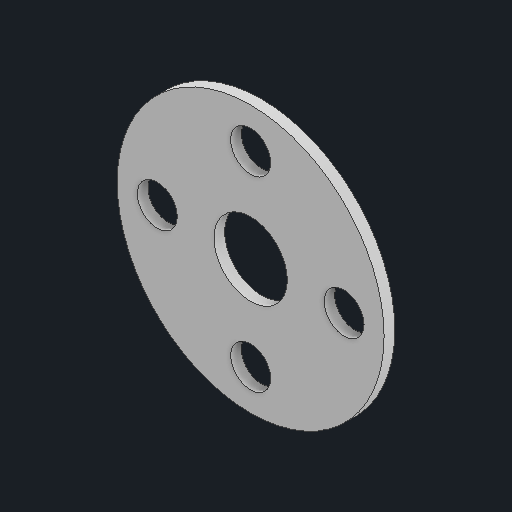
# Autodesk Inventor part: Separador_pitch_0p8_R1
Saved by Autodesk Inventor 2027.2 (Build 312334000, 334)
## iProperties
Created: 2026-11-13
Part Number: Separador_pitch_0p8_R1
Material: Genérico
Document SubType Name: Modeling
Designer: alexa
Mass: 0.209701 g
Surface Area: 6.18501 cm^2
Volume: 0.209701 cm^3
Density: 1 g/cm^3
Appearance: Valor por defecto
Author: alexa
Autodesk Inventor part; units mm, degrees
ref_plane "YZ Plane" through (0, 0, 0) normal (1, 0, 0) x (0, 1, 0)
ref_plane "XZ Plane" through (0, 0, 0) normal (0, 1, 0) x (-1, 0, 0)
ref_plane "XY Plane" through (0, 0, 0) normal (0, 0, 1) x (1, 0, 0)
sketch "Disco_20_centro_5p5_patron_14" plane through (0, 0, 0) normal (0, 0, 1) x (1, 0, 0)
  circle A0 centre (0, 0) radius 10
  circle A1 centre (0, 0) radius 2.75
  circle A2 centre (7, 0) radius 1.5
  circle A3 centre (0, 7) radius 1.5
  circle A4 centre (-7, 0) radius 1.5
  circle A5 centre (0, -7) radius 1.5
  constraints: 6 centre point
extrude "Separacion_axial_0p8_mm" add sketch "Disco_20_centro_5p5_patron_14" against normal blind 0.8
